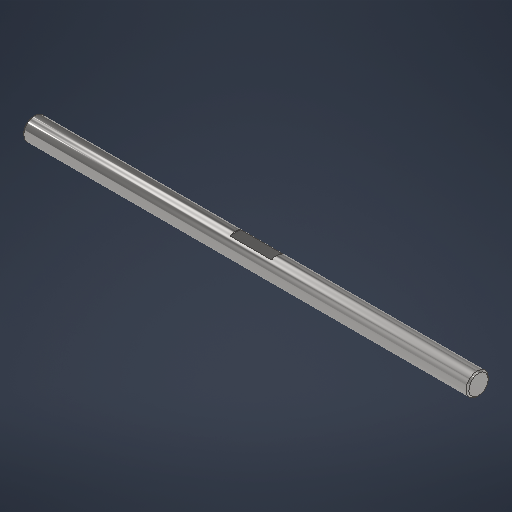
# Autodesk Inventor part: CNV-MEC-01
Saved by Autodesk Inventor 2026.1 (Build 301233020, 233B)
## iProperties
Created: 2026-11-13
Part Number: CNV-MEC-01
Material: Steel
Description: Drive shaft Ø8 × 160, set-screw flat
Document SubType Name: Modeling
Designer: JoshLev
Mass: 62.9322 g
Surface Area: 41.0646 cm^2
Volume: 8.01684 cm^3
Density: 7.85 g/cm^3
Appearance: Steel - Polished
Author: jleva
Revision Number: A
Autodesk Inventor part; units mm, degrees
ref_plane "YZ Plane" through (0, 0, 0) normal (1, 0, 0) x (0, 1, 0)
ref_plane "XZ Plane" through (0, 0, 0) normal (0, 1, 0) x (-1, 0, 0)
sketch "Sketch1" plane through (0, 0, 0) normal (1, 0, 0) x (0, 1, 0)
  circle A0 centre (0, 0) radius 4
  dimension "d0" = 8
  constraints: 1 centre point, 1 coincident
  measures "d0" diameter of A0
extrude "Rod" add sketch "Sketch1" along normal blind 160
ref_plane "FlatStartPlane" through (72.5, 0, 0) normal (-1, 0, 0) x (0, 0, 1)
sketch "Sketch2" plane through (0, 0, 0) normal (0, 0, 1) x (1, 0, 0)
  line L0 (72.5, -6) -> (72.5, 8) projected
  line L1 (-32, 0) -> (192, 0) projected
  line L2 (72.5, 3.5) -> (87.5, 3.5)
  line L3 (87.5, 3.5) -> (87.5, 6)
  line L4 (87.5, 6) -> (72.5, 6)
  line L5 (72.5, 6) -> (72.5, 3.5)
  point P0 (0, 0)
  dimension "d5" = 15
  dimension "d6" = 3.5
  dimension "d7" = 2.5
  constraints: 8 end point, 2 parallel, 1 collinear, 1 horizontal, 1 perpendicular
  measures "d5" distance of L2.start L2.end
  measures "d6" distance between parallel lines of L1 L2
  measures "d7" distance of L4.end L2.start
extrude "SetScrewFlat" cut sketch "Sketch2" along normal through all both and the other way through all
chamfer "EndChamfers" distance 0.5 angle 45 2 edges at (160, -4, 0) (0, -4, 0)
equation "\"d0\" = shaft_d"
equation "\"d1\" = shaft_L"
equation "\"d5\" = flat_len"
equation "\"d6\" = 0.5 * shaft_d - flat_depth"
equation "\"d10\" = chamfer"
equation "\"shaft_d\" = 8"
equation "\"shaft_L\" = 160"
equation "\"flat_depth\" = 0.5"
equation "\"flat_len\" = 15"
equation "\"chamfer\" = 0.5"
equation "\"d4\" = 0.5 * flat_len - flat_x"
equation "\"flat_x\" = 80"
body "Solid1"
